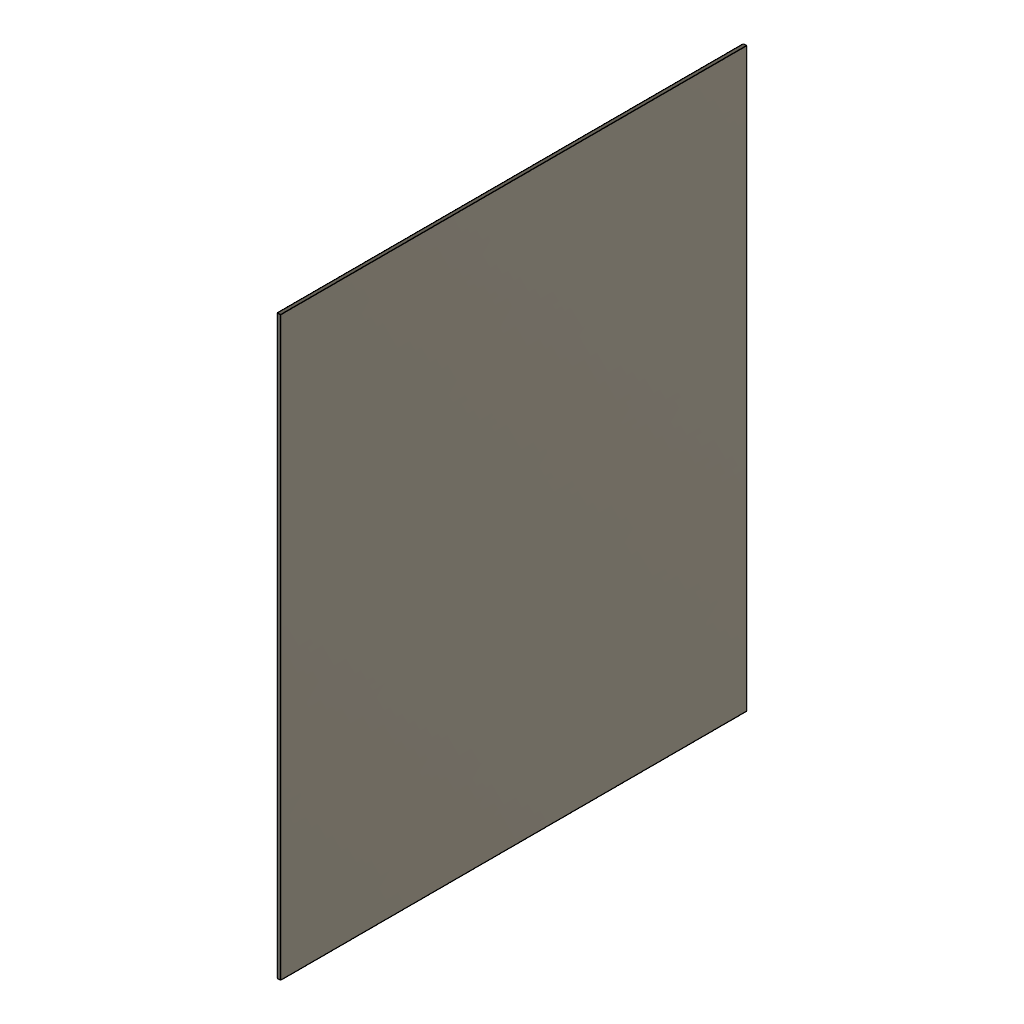
Blotting_paper (Autodesk Fusion 360 design; units mm, degrees)
part number: 2026-11-24-17-05-53-100
Autodesk Fusion 360 part; units mm, degrees
derive "DerivedContext1"
sketch "Sketch1" plane through (-71.1833, 25.7012, -0.92) normal (-1, 0, 0) x (0, -1, 0)
  line L0 (39.4024, 7.84) -> (37.4024, 7.84)
  line L1 (37.4024, 7.84) -> (37.4024, 1.84)
  line L2 (37.4024, 1.84) -> (39.4024, 1.84)
  line L3 (39.4024, 1.84) -> (39.4024, 7.84)
  line L4 (37.4024, 1.84) -> (51.4435, 1.84)
  line L5 (51.4435, 1.84) -> (51.4435, 19.2017)
  line L6 (51.4435, 19.2017) -> (37.4024, 19.2017)
  line L7 (37.4024, 19.2017) -> (37.4024, 1.84)
  constraint horizontal L4
  constraint vertical L5
  constraint horizontal L6
  constraint vertical L7
  constraint coincident L1.end L2.start
extrude "Extrude1" add sketch "Sketch1" along normal blind 0.1
